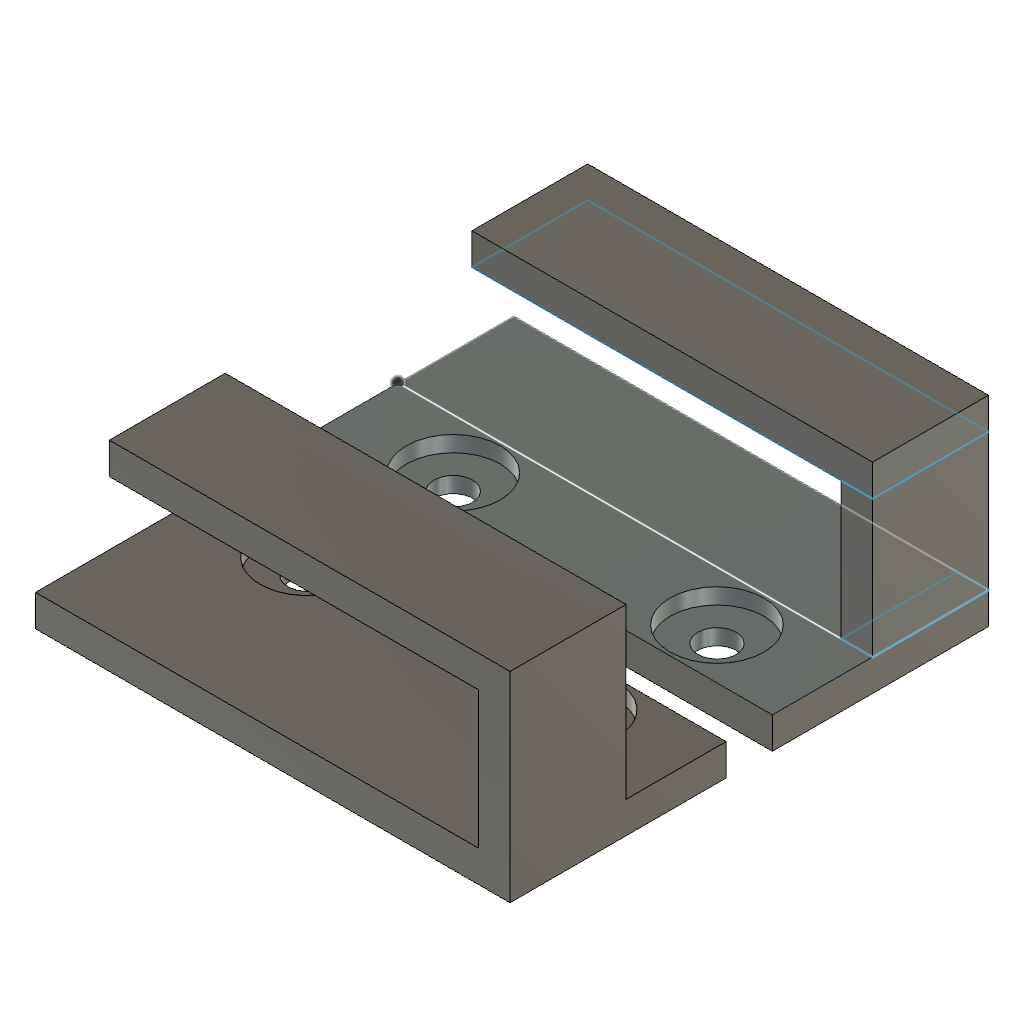
optiplexBigPowerBrick (Autodesk Fusion 360 design; units mm, degrees)
part number: 2026-08-10-19-56-16-923
Autodesk Fusion 360 part; units mm, degrees
sketch "Sketch1" plane through (0, 0, 0) normal (0, 0, 1) x (1, 0, 0)
  line L0 (-28, 37) -> (62, 37)
  line L1 (62, 37) -> (62, 18)
  line L2 (62, 18) -> (-28, 18)
  line L3 (-28, 18) -> (-28, 37)
  dimension "d1" = 90
  dimension "d2" = 19
  constraint horizontal L0
  constraint vertical L1
  constraint horizontal L2
  constraint vertical L3
  measures "d1" distance of L0.start L0.end
  measures "d2" distance of L0.start L2.end
extrude "Extrude1" add sketch "Sketch1" along normal blind 6 makes body 1
sketch "Sketch2" plane through (0, 0, 6) normal (0, 0, 1) x (-1, 0, 0)
  line L0 (28, -37) -> (28, -18)
  line L1 (28, -18) -> (-62, -18)
  line L2 (-62, -18) -> (-62, -37)
  line L3 (-62, -37) -> (28, -37)
ref_plane "WorkPlane1" through (17, 27.5, 6) normal (0, 0, 1) x (-1, 0, 0)
sketch "Sketch3" plane through (0, 0, 6) normal (0, 0, 1) x (1, 0, 0)
  line L0 (17, 37) -> (17, 18)
  circle A0 centre (-8, 27.5) radius 8.9
  circle A1 centre (42, 27.5) radius 8.9
  circle A2 centre (-8, 27.5) radius 3.65
  circle A3 centre (42, 27.5) radius 3.65
  dimension "d13" = 17.8
  dimension "d14" = 17.8
  dimension "d15" = 7.3
  dimension "d16" = 7.3
  constraint vertical L0
  constraint concentric A0 A2
  constraint concentric A1 A3
  measures "d13" diameter of A0
  measures "d14" diameter of A1
  measures "d15" diameter of A2
  measures "d16" diameter of A3
extrude "Extrude2" cut sketch "Sketch3" against normal blind 7 contours A2 | A3 bodies 1
extrude "Extrude3" cut sketch "Sketch3" against normal blind 3 bodies 1
sketch "Sketch4" plane through (0, 0, 0) normal (0, 0, 1) x (1, 0, 0)
  line L0 (-21, 37) -> (55, 37)
  line L1 (55, 37) -> (55, 39)
  line L2 (55, 39) -> (-21, 39)
  line L3 (-21, 39) -> (-21, 37)
  dimension "d21" = 76
  dimension "d22" = 2
  constraint horizontal L0
  constraint vertical L1
  constraint horizontal L2
  constraint vertical L3
  measures "d21" distance of L0.start L0.end
  measures "d22" distance of L0.start L2.end
sketch "Sketch7" plane through (0, 0, 6) normal (0, 0, 1) x (-1, 0, 0)
  circle A0 centre (-42, -27.5) radius 8.9
  circle A1 centre (8, -27.5) radius 8.9
  line L0 (28, -18) -> (-62, -18)
  line L1 (-62, -18) -> (-62, -37)
  line L2 (-62, -37) -> (28, -37)
  line L3 (28, -37) -> (28, -18)
  line L4 (28, -37) -> (-62, -37)
  line L5 (-62, -37) -> (-62, -59)
  line L6 (-62, -59) -> (28, -59)
  line L7 (28, -59) -> (28, -37)
  dimension "d37" = 90
  dimension "d38" = 22
  constraint horizontal L4
  constraint vertical L5
  constraint horizontal L6
  constraint vertical L7
  constraint coincident L2.end L3.start
  measures "d37" distance of L2.end L1.end
  measures "d38" distance of L2.end L6.end
extrude "Extrude7" add sketch "Sketch7" against normal blind 6 contours L2 L4 L5 L6 L7 bodies 1
sketch "Sketch8" plane through (0, 0, 6) normal (0, 0, 1) x (-1, 0, 0)
  line L0 (-62, -59) -> (-56, -59)
  line L1 (-56, -59) -> (-56, -37)
  line L2 (-56, -37) -> (-62, -37)
  line L3 (-62, -37) -> (-62, -59)
  dimension "d41" = 6
  dimension "d42" = 22
  constraint horizontal L0
  constraint vertical L1
  constraint horizontal L2
  constraint vertical L3
  measures "d41" distance of L0.start L0.end
  measures "d42" distance of L0.start L2.end
extrude "Extrude8" add sketch "Sketch8" along normal blind 26 bodies 1
sketch "Sketch9" plane through (0, 0, 32) normal (0, 0, 1) x (-1, 0, 0)
  line L0 (-62, -37) -> (-62, -59)
  line L1 (-62, -59) -> (-56, -59)
  line L2 (-56, -59) -> (-56, -37)
  line L3 (-56, -37) -> (-62, -37)
sketch "Sketch10" plane through (0, 0, 32) normal (0, 0, 1) x (-1, 0, 0)
  line L0 (-62, -59) -> (14, -59)
  line L1 (14, -59) -> (14, -37)
  line L2 (14, -37) -> (-62, -37)
  line L3 (-62, -37) -> (-62, -59)
  dimension "d45" = 76
  dimension "d46" = 22
  constraint horizontal L0
  constraint vertical L1
  constraint horizontal L2
  constraint vertical L3
  measures "d45" distance of L0.start L0.end
  measures "d46" distance of L0.start L2.end
extrude "Extrude9" add sketch "Sketch10" along normal blind 6 bodies 1
mirror "Mirror1" about plane through (62, 18, 0) normal (0, -1, 0) of bodies 1 makes body 2
move_face "MoveFace1" by (0, -4.3734, 0) 1 faces at (7.7505, -15.2616, 6) on bodies 2
move_body "Move1" bodies 2 to x (1, 0, 0) y (0, 1, 0) z (0, 0, 1) at (0, -8.7469, 0)
